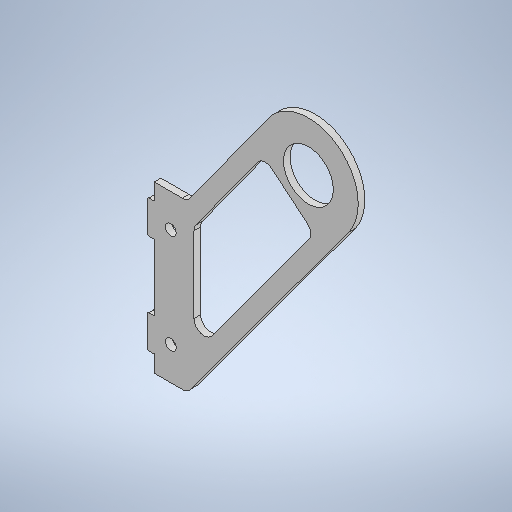
# Autodesk Inventor part: plate_prAltNew
Saved by Autodesk Inventor 2025.3 (Build 293356000, 356)
## iProperties
Created: 2026-10-19
Part Number: plate_prAltNew
Material: 一般
Document SubType Name: Modeling
Designer: yunto
Density: 1 g/cm^3
Appearance: 既定
Author: yunto
Autodesk Inventor part; units mm, degrees
ref_plane "YZ Plane" through (0, 0, 0) normal (1, 0, 0) x (0, 1, 0)
ref_plane "XZ Plane" through (0, 0, 0) normal (0, 1, 0) x (-1, 0, 0)
ref_plane "XY Plane" through (0, 0, 0) normal (0, 0, 1) x (1, 0, 0)
sketch "スケッチ1" plane through (0, 0, 0) normal (0, 0, 1) x (1, 0, 0)
  circle A0 centre (41.5331, 50) radius 15
  circle A1 centre (41.5331, 50) radius 7.5
  line L0 (-5, 25) -> (5, 25)
  line L1 (5, -25) -> (-5, -25)
  line L2 (-5, -25) -> (-5, 25)
  line L3 (-5, 0) -> (0, 0) construction
  line L4 (0, 15) -> (0, -15) construction
  circle A2 centre (0, 15) radius 1.6
  circle A3 centre (0, -15) radius 1.6
  line L5 (-7.1, 20) -> (-5, 20)
  line L6 (-5, 20) -> (-5, 10)
  line L7 (-5, 10) -> (-7.1, 10)
  line L8 (-7.1, 10) -> (-7.1, 20)
  line L9 (-7.1, -10) -> (-5, -10)
  line L10 (-5, -10) -> (-5, -20)
  line L11 (-5, -20) -> (-7.1, -20)
  line L12 (-7.1, -20) -> (-7.1, -10)
  line L13 (5, 25) -> (29.3686, 58.7763)
  line L14 (5, -25) -> (53.6175, 41.1136)
  line L15 (0, 0) -> (41.5331, 50) construction
  line L16 (7, 19.2264) -> (27.9584, 48.276)
  line L17 (27.9584, 48.276) -> (43.3043, 35.5288)
  line L18 (43.3043, 35.5288) -> (7, -13.8404)
  line L19 (7, -13.8404) -> (7, 19.2264)
  point P0 (-7.1, 15)
  point P1 (-7.1, -15)
  point P2 (31.9486, 38.4615)
  point P3 (26.8819, 46.784)
  point P4 (42.9658, 35.0686)
  dimension "d0" = 15
  dimension "d1" = 30
  dimension "d2" = 10
  dimension "d3" = 3.2
  dimension "d4" = 5
  dimension "d5" = 30
  dimension "d6" = 10
  dimension "d7" = 15
  dimension "d8" = 15
  dimension "d9" = 50
  dimension "d10" = 65
  dimension "d11" = 2.1
  dimension "d12" = 50
  dimension "d19" = 5
  dimension "d20" = 5
  dimension "d21" = 10
  dimension "d22" = 12
  constraints: 40 end point, 8 parallel, 4 centre point, 4 coincident, 4 horizontal, 4 midpoint, 3 equal length, 3 perpendicular, 2 point on circle, 2 tangent, 1 collinear, 1 equal radius, 1 point on line, 1 vertical
  measures "d0" diameter of A1
  measures "d1" diameter of A0
  measures "d2" distance of L0.start L13.start
  measures "d3" diameter of A2
  measures "d4" distance of L3.start L15.start
  measures "d5" distance of L4.start L4.end
  measures "d6" distance of L7.end L5.start
  measures "d7" vertical distance of L3.start point (-7.1, 15)
  measures "d8" vertical distance of point (-7.1, -15) L3.start
  measures "d9" distance of L2.start L0.start
  measures "d10" distance of A0.centre L15.start
  measures "d11" distance of L11.start L11.end
  measures "d12" vertical distance of A0.centre L15.start
  measures "d19" distance between parallel lines of L14 L18
  measures "d20" distance between parallel lines of L13 L16
  measures "d21" distance from line of A0.centre L17
  measures "d22" distance between parallel lines of L2 L19
extrude "押し出し1" add sketch "スケッチ1" along normal blind 2 contours A0 L18 L17 L16 | A0 L16 L19 L18 L14 L1 L2 L0 L13 | L2 L7 L8 L5 | L11 L12 L9 L2 picked at (36.1784, 42.5441)
fillet "フィレット1" radius 3 6 edges at (5, -25, 1) (5, 25, 1) (7, 19.2264, 1) (7, -13.8404, 1) (27.9584, 48.276, 1) (43.3043, 35.5288, 1)
fillet "フィレット2" radius 0.5 4 edges at (-7.1, -20, 1) (-7.1, -10, 1) (-7.1, 10, 1) (-7.1, 20, 1)
equation "\"d8\" = d7"
equation "\"d10\" = d13"
equation "\"d12\" = d14"
equation "\"d20\" = d19"
equation "\"d13\" = 65"
equation "\"d14\" = 50"
